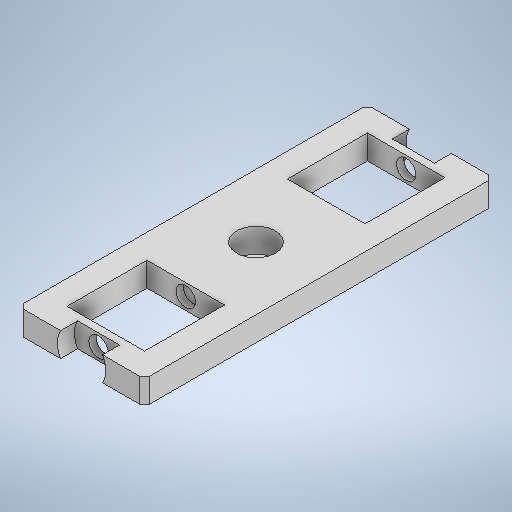
# Autodesk Inventor part: mini_piñon1
Saved by Autodesk Inventor 2025.2 (Build 292293000, 293)
## iProperties
Created: 2025-03-18
Part Number: mini_piñon1
Material: Generic
Document SubType Name: Modeling
Designer: laura
Density: 1 g/cm^3
Appearance: Default
Author: laura
Autodesk Inventor part; units mm, degrees
ref_plane "YZ Plane" through (0, 0, 0) normal (1, 0, 0) x (0, 1, 0)
ref_plane "XZ Plane" through (0, 0, 0) normal (0, 1, 0) x (-1, 0, 0)
ref_plane "XY Plane" through (0, 0, 0) normal (0, 0, 1) x (1, 0, 0)
sketch "Sketch2" plane through (0, 0, 0) normal (0, 1, 0) x (-1, 0, 0)
  line L0 (0, 72) -> (0, -72)
  line L1 (26, 72) -> (26, -72)
  line L2 (16, 29) -> (0, 29)
  line L3 (16, -62) -> (0, -62)
  line L4 (26, -72) -> (0, -72)
  line L5 (26, 72) -> (0, 72)
  line L6 (0, 62) -> (16, 62)
  line L7 (0, 0) -> (26, 0) construction
  line L8 (0, -72) -> (0, -72) construction
  line L9 (0, 72) -> (0, 72) construction
  line L10 (-26, 72) -> (-26, -72)
  line L11 (-16, 29) -> (0, 29)
  line L12 (-16, -62) -> (0, -62)
  line L13 (-26, -72) -> (0, -72)
  line L14 (-26, 72) -> (0, 72)
  line L15 (0, 62) -> (-16, 62)
  line L16 (16, -62) -> (16, 62)
  line L17 (-16, -62) -> (-16, 62)
  line L18 (-16, -29) -> (16, -29)
  point P0 (-26, 0)
  point P1 (-16, 29)
  point P2 (0, 62)
  point P3 (0, -62)
  dimension "d7" = 52
  dimension "d10" = 10
  dimension "d11" = 10
  dimension "d23" = 32
  dimension "d24" = 33
  dimension "d44" = 33
  dimension "d49" = 58
  constraints: 39 end point, 10 symmetric about line, 6 horizontal, 6 point on line, 5 perpendicular, 2 midpoint, 2 vertical, 1 coincident
  measures "d7" diameter of L1 L0
  measures "d10" distance between parallel lines of L5 L6
  measures "d11" distance between parallel lines of L4 L3
  measures "d23" diameter of L16 L0
  measures "d24" distance between parallel lines of L18 L3
  measures "d44" distance between parallel lines of L6 L2
  measures "d49" distance between parallel lines of L2 L18
extrude "Extrusion1" add sketch "Sketch2" along normal mid plane 10 contours L5 L1 L4 L0 L3 L16 L6 | L0 L15 L17 L12 L13 L10 L14
extrude "Extrusion4" add sketch "Sketch2" along normal mid plane 10 contours L2 L16 L18 L0 | L0 L18 L17 L11
chamfer "Chamfer1" distance 2 angle 45 4 edges at (-26, 0, 72) (26, 0, 72) (-26, 0, -72) (26, 0, -72)
sketch "Sketch3" plane through (0, 5, 0) normal (0, 1, 0) x (1, 0, 0)
  line L0 (26, -70) -> (26, 70) projected
  line L1 (26, 0) -> (-26, 0) construction
  line L2 (-26, 70) -> (-26, -70) projected
  line L3 (-16, -29) -> (16, -29) projected
  line L4 (0, -29) -> (0, 29)
  line L5 (16, 29) -> (-16, 29) projected
  circle A0 centre (0, 0) radius 8
  dimension "d37" = 16
  constraints: 4 end point, 4 midpoint, 1 centre point, 1 coincident
  measures "d37" diameter of A0
extrude "Extrusion6" cut sketch "Sketch3" against normal through all
sketch "Sketch4" plane through (24, -5, -72) normal (0, 0, -1) x (-1, 0, 0)
  circle A0 centre (24, 5) radius 10
  point P0 (24, 5)
  dimension "d40" = 20
  constraints: 1 centre point, 1 coincident
  measures "d40" diameter of A0
extrude "Extrusion7" cut sketch "Sketch4" against normal blind 7
mirror "Mirror1" about plane through (0, 0, 0) normal (0, 0, 1) of "Extrusion7"
sketch "Sketch5" plane through (-16, 5, 29) normal (0, 0, 1) x (1, 0, 0)
  circle A0 centre (16, -5) radius 4
  dimension "d46" = 8
  constraints: 1 centre point, 1 coincident
  measures "d46" diameter of A0
extrude "Extrusion8" cut sketch "Sketch5" along normal blind 40 and the other way blind 3
mirror "Mirror2" about plane through (0, 0, 0) normal (0, 0, 1) of "Extrusion8"
body "Solid1"
